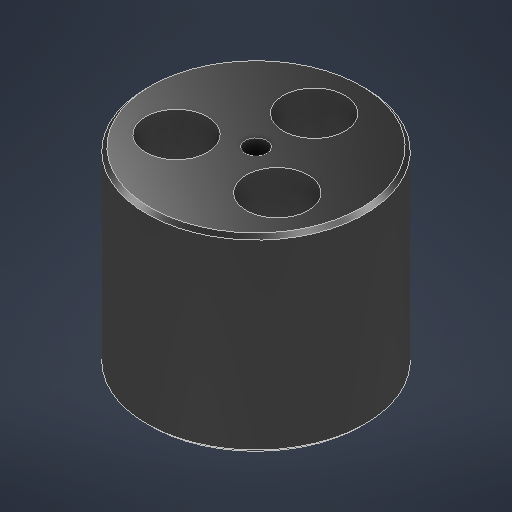
# Autodesk Inventor part: Revolving cylinder body
Saved by Autodesk Inventor 2026.3 (Build 303398000, 398)
## iProperties
Created: 2026-11-02
Part Number: Revolving cylinder body
Material: Steel
Document SubType Name: Modeling
Designer: ADMIN
Density: 7.85 g/cm^3
Appearance: Glossy - Black
Author: ADMIN
Autodesk Inventor part; units mm, degrees
ref_plane "YZ Plane" through (0, 0, 0) normal (1, 0, 0) x (0, 1, 0)
ref_plane "XZ Plane" through (0, 0, 0) normal (0, 1, 0) x (-1, 0, 0)
ref_plane "XY Plane" through (0, 0, 0) normal (0, 0, 1) x (1, 0, 0)
sketch "Sketch1" plane through (0, 0, 0) normal (0, 1, 0) x (-1, 0, 0)
  circle A0 centre (0, 0) radius 15
  dimension "d0" = 30
  constraints: 1 centre point, 1 coincident
  measures "d0" diameter of A0
extrude "Extrusion1" add sketch "Sketch1" along normal mid plane 26
sketch "Sketch3" plane through (0, 13, 0) normal (0, 1, 0) x (1, 0, 0)
  point P0 (0, 0)
  point P1 (0, 0)
  constraints: 1 coincident
hole "Hole1" at (0, 13, 0) direction (0, -1, 0) diameter 3 end through all
sketch "Sketch4" plane through (0, 13, 0) normal (0, 1, 0) x (1, 0, 0)
  point P0 (0, 0)
  point P1 (0, 8)
  point P2 (-6.9282, -4)
  point P3 (6.9282, -4)
  dimension "d11" = 8
  dimension "d14" = 360
  constraints: 1 vertical alignment, 4 other
  measures "d11" distance of point (0, 0) point (0, 8)
hole "Hole2" at (0, 13, -8) at (-6.9282, 13, 4) at (6.9282, 13, 4) direction (0, -1, 0) diameter 8.5 end through all
chamfer "Chamfer1" distance 0.5 angle 45 2 edges at (15, 13, 0) (15, -13, 0)
body "Solid1"
